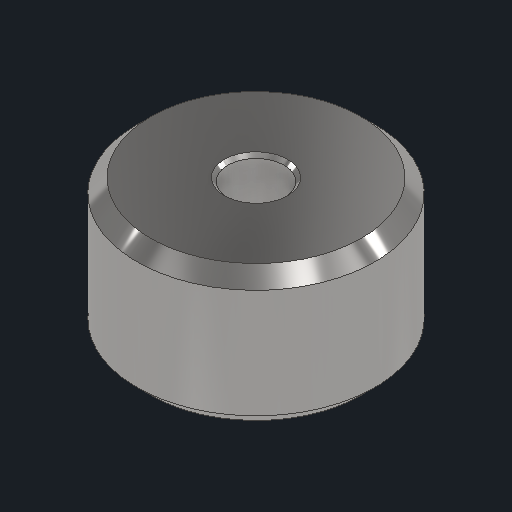
# Autodesk Inventor part: weight_arm2
Saved by Autodesk Inventor 2027.1 (Build 311270010, 270A)
## iProperties
Created: 2026-10-11
Part Number: weight_arm2
Material: Aluminum 6061
Document SubType Name: Modeling
Designer: lucao
Density: 2.7 g/cm^3
Appearance: Steel - Polished
Mass: 47.8718 g
Surface Area: 42.5396 cm^2
Volume: 17.7303 cm^3
Author: lucao
Autodesk Inventor part; units mm, degrees
ref_plane "YZ Plane" through (0, 0, 0) normal (1, 0, 0) x (0, 1, 0)
ref_plane "XZ Plane" through (0, 0, 0) normal (0, 1, 0) x (-1, 0, 0)
ref_plane "XY Plane" through (0, 0, 0) normal (0, 0, 1) x (1, 0, 0)
sketch "Sketch1" plane through (0, 0, 0) normal (0, 1, 0) x (-1, 0, 0)
  circle A0 centre (0, 0) radius 17.5
  circle A1 centre (0, 0) radius 4.15
  dimension "d0" = 35
  dimension "d1" = 8.3
  constraints: 2 centre point, 2 coincident
  measures "d0" diameter of A0
  measures "d1" diameter of A1
extrude "Extrusion1" add sketch "Sketch1" along normal blind 20
chamfer "Chamfer1" distance 2 angle 45 2 edges at (17.5, 20, 0) (17.5, 0, 0)
chamfer "Chamfer2" distance 0.5 angle 45 2 edges at (4.15, 20, 0) (4.15, 0, 0)
body "Solid1"
